Autodesk Fusion 360 part; units mm, degrees
(part 2 of 3)
sketch "spacer_pads" plane through (0, 0, 7.25) normal (0, 0, 1) x (1, 0, 0) in component "drop_plate"
  line L0 (-80, -68) -> (-77, -68)
  line L1 (-77, -68) -> (-77, -62)
  line L2 (-77, -62) -> (-80, -62)
  line L3 (-80, -62) -> (-80, -68)
  line L4 (-53, -68) -> (-50, -68)
  line L5 (-50, -68) -> (-50, -62)
  line L6 (-50, -62) -> (-53, -62)
  line L7 (-53, -62) -> (-53, -68)
  line L8 (-68, -80) -> (-62, -80)
  line L9 (-62, -80) -> (-62, -77)
  line L10 (-62, -77) -> (-68, -77)
  line L11 (-68, -77) -> (-68, -80)
  line L12 (-68, -53) -> (-62, -53)
  line L13 (-62, -53) -> (-62, -50)
  line L14 (-62, -50) -> (-68, -50)
  line L15 (-68, -50) -> (-68, -53)
  line L16 (-80, -35.5) -> (-77, -35.5)
  line L17 (-77, -35.5) -> (-77, -29.5)
  line L18 (-77, -29.5) -> (-80, -29.5)
  line L19 (-80, -29.5) -> (-80, -35.5)
  line L20 (-53, -35.5) -> (-50, -35.5)
  line L21 (-50, -35.5) -> (-50, -29.5)
  line L22 (-50, -29.5) -> (-53, -29.5)
  line L23 (-53, -29.5) -> (-53, -35.5)
  line L24 (-68, -47.5) -> (-62, -47.5)
  line L25 (-62, -47.5) -> (-62, -44.5)
  line L26 (-62, -44.5) -> (-68, -44.5)
  line L27 (-68, -44.5) -> (-68, -47.5)
  line L28 (-68, -20.5) -> (-62, -20.5)
  line L29 (-62, -20.5) -> (-62, -17.5)
  line L30 (-62, -17.5) -> (-68, -17.5)
  line L31 (-68, -17.5) -> (-68, -20.5)
  line L32 (-80, -3) -> (-77, -3)
  line L33 (-77, -3) -> (-77, 3)
  line L34 (-77, 3) -> (-80, 3)
  line L35 (-80, 3) -> (-80, -3)
  line L36 (-53, -3) -> (-50, -3)
  line L37 (-50, -3) -> (-50, 3)
  line L38 (-50, 3) -> (-53, 3)
  line L39 (-53, 3) -> (-53, -3)
  line L40 (-68, -15) -> (-62, -15)
  line L41 (-62, -15) -> (-62, -12)
  line L42 (-62, -12) -> (-68, -12)
  line L43 (-68, -12) -> (-68, -15)
  line L44 (-68, 12) -> (-62, 12)
  line L45 (-62, 12) -> (-62, 15)
  line L46 (-62, 15) -> (-68, 15)
  line L47 (-68, 15) -> (-68, 12)
  line L48 (-80, 29.5) -> (-77, 29.5)
  line L49 (-77, 29.5) -> (-77, 35.5)
  line L50 (-77, 35.5) -> (-80, 35.5)
  line L51 (-80, 35.5) -> (-80, 29.5)
  line L52 (-53, 29.5) -> (-50, 29.5)
  line L53 (-50, 29.5) -> (-50, 35.5)
  line L54 (-50, 35.5) -> (-53, 35.5)
  line L55 (-53, 35.5) -> (-53, 29.5)
  line L56 (-68, 17.5) -> (-62, 17.5)
  line L57 (-62, 17.5) -> (-62, 20.5)
  line L58 (-62, 20.5) -> (-68, 20.5)
  line L59 (-68, 20.5) -> (-68, 17.5)
  line L60 (-68, 44.5) -> (-62, 44.5)
  line L61 (-62, 44.5) -> (-62, 47.5)
  line L62 (-62, 47.5) -> (-68, 47.5)
  line L63 (-68, 47.5) -> (-68, 44.5)
  line L64 (-80, 62) -> (-77, 62)
  line L65 (-77, 62) -> (-77, 68)
  line L66 (-77, 68) -> (-80, 68)
  line L67 (-80, 68) -> (-80, 62)
  line L68 (-53, 62) -> (-50, 62)
  line L69 (-50, 62) -> (-50, 68)
  line L70 (-50, 68) -> (-53, 68)
  line L71 (-53, 68) -> (-53, 62)
  line L72 (-68, 50) -> (-62, 50)
  line L73 (-62, 50) -> (-62, 53)
  line L74 (-62, 53) -> (-68, 53)
  line L75 (-68, 53) -> (-68, 50)
  line L76 (-68, 77) -> (-62, 77)
  line L77 (-62, 77) -> (-62, 80)
  line L78 (-62, 80) -> (-68, 80)
  line L79 (-68, 80) -> (-68, 77)
  line L80 (-47.5, -68) -> (-44.5, -68)
  line L81 (-44.5, -68) -> (-44.5, -62)
  line L82 (-44.5, -62) -> (-47.5, -62)
  line L83 (-47.5, -62) -> (-47.5, -68)
  line L84 (-20.5, -68) -> (-17.5, -68)
  line L85 (-17.5, -68) -> (-17.5, -62)
  line L86 (-17.5, -62) -> (-20.5, -62)
  line L87 (-20.5, -62) -> (-20.5, -68)
  line L88 (-35.5, -80) -> (-29.5, -80)
  line L89 (-29.5, -80) -> (-29.5, -77)
  line L90 (-29.5, -77) -> (-35.5, -77)
  line L91 (-35.5, -77) -> (-35.5, -80)
  line L92 (-35.5, -53) -> (-29.5, -53)
  line L93 (-29.5, -53) -> (-29.5, -50)
  line L94 (-29.5, -50) -> (-35.5, -50)
  line L95 (-35.5, -50) -> (-35.5, -53)
  line L96 (-47.5, -35.5) -> (-44.5, -35.5)
  line L97 (-44.5, -35.5) -> (-44.5, -29.5)
  line L98 (-44.5, -29.5) -> (-47.5, -29.5)
  line L99 (-47.5, -29.5) -> (-47.5, -35.5)
  line L100 (-20.5, -35.5) -> (-17.5, -35.5)
  line L101 (-17.5, -35.5) -> (-17.5, -29.5)
  line L102 (-17.5, -29.5) -> (-20.5, -29.5)
  line L103 (-20.5, -29.5) -> (-20.5, -35.5)
  line L104 (-35.5, -47.5) -> (-29.5, -47.5)
  line L105 (-29.5, -47.5) -> (-29.5, -44.5)
  line L106 (-29.5, -44.5) -> (-35.5, -44.5)
  line L107 (-35.5, -44.5) -> (-35.5, -47.5)
  line L108 (-35.5, -20.5) -> (-29.5, -20.5)
  line L109 (-29.5, -20.5) -> (-29.5, -17.5)
  line L110 (-29.5, -17.5) -> (-35.5, -17.5)
  line L111 (-35.5, -17.5) -> (-35.5, -20.5)
  line L112 (-47.5, -3) -> (-44.5, -3)
  line L113 (-44.5, -3) -> (-44.5, 3)
  line L114 (-44.5, 3) -> (-47.5, 3)
  line L115 (-47.5, 3) -> (-47.5, -3)
  line L116 (-20.5, -3) -> (-17.5, -3)
  line L117 (-17.5, -3) -> (-17.5, 3)
  line L118 (-17.5, 3) -> (-20.5, 3)
  line L119 (-20.5, 3) -> (-20.5, -3)
  line L120 (-35.5, -15) -> (-29.5, -15)
  line L121 (-29.5, -15) -> (-29.5, -12)
  line L122 (-29.5, -12) -> (-35.5, -12)
  line L123 (-35.5, -12) -> (-35.5, -15)
  line L124 (-35.5, 12) -> (-29.5, 12)
  line L125 (-29.5, 12) -> (-29.5, 15)
  line L126 (-29.5, 15) -> (-35.5, 15)
  line L127 (-35.5, 15) -> (-35.5, 12)
  line L128 (-47.5, 29.5) -> (-44.5, 29.5)
  line L129 (-44.5, 29.5) -> (-44.5, 35.5)
  line L130 (-44.5, 35.5) -> (-47.5, 35.5)
  line L131 (-47.5, 35.5) -> (-47.5, 29.5)
  line L132 (-20.5, 29.5) -> (-17.5, 29.5)
  line L133 (-17.5, 29.5) -> (-17.5, 35.5)
  line L134 (-17.5, 35.5) -> (-20.5, 35.5)
  line L135 (-20.5, 35.5) -> (-20.5, 29.5)
  line L136 (-35.5, 17.5) -> (-29.5, 17.5)
  line L137 (-29.5, 17.5) -> (-29.5, 20.5)
  line L138 (-29.5, 20.5) -> (-35.5, 20.5)
  line L139 (-35.5, 20.5) -> (-35.5, 17.5)
  line L140 (-35.5, 44.5) -> (-29.5, 44.5)
  line L141 (-29.5, 44.5) -> (-29.5, 47.5)
  line L142 (-29.5, 47.5) -> (-35.5, 47.5)
  line L143 (-35.5, 47.5) -> (-35.5, 44.5)
  line L144 (-47.5, 62) -> (-44.5, 62)
  line L145 (-44.5, 62) -> (-44.5, 68)
  line L146 (-44.5, 68) -> (-47.5, 68)
  line L147 (-47.5, 68) -> (-47.5, 62)
  line L148 (-20.5, 62) -> (-17.5, 62)
  line L149 (-17.5, 62) -> (-17.5, 68)
  line L150 (-17.5, 68) -> (-20.5, 68)
  line L151 (-20.5, 68) -> (-20.5, 62)
  line L152 (-35.5, 50) -> (-29.5, 50)
  line L153 (-29.5, 50) -> (-29.5, 53)
  line L154 (-29.5, 53) -> (-35.5, 53)
  line L155 (-35.5, 53) -> (-35.5, 50)
  line L156 (-35.5, 77) -> (-29.5, 77)
  line L157 (-29.5, 77) -> (-29.5, 80)
  line L158 (-29.5, 80) -> (-35.5, 80)
  line L159 (-35.5, 80) -> (-35.5, 77)
  line L160 (-15, -68) -> (-12, -68)
  line L161 (-12, -68) -> (-12, -62)
  line L162 (-12, -62) -> (-15, -62)
  line L163 (-15, -62) -> (-15, -68)
  line L164 (12, -68) -> (15, -68)
  line L165 (15, -68) -> (15, -62)
  line L166 (15, -62) -> (12, -62)
  line L167 (12, -62) -> (12, -68)
  line L168 (-3, -80) -> (3, -80)
  line L169 (3, -80) -> (3, -77)
  line L170 (3, -77) -> (-3, -77)
  line L171 (-3, -77) -> (-3, -80)
  line L172 (-3, -53) -> (3, -53)
  line L173 (3, -53) -> (3, -50)
  line L174 (3, -50) -> (-3, -50)
  line L175 (-3, -50) -> (-3, -53)
  line L176 (-15, -35.5) -> (-12, -35.5)
  line L177 (-12, -35.5) -> (-12, -29.5)
  line L178 (-12, -29.5) -> (-15, -29.5)
  line L179 (-15, -29.5) -> (-15, -35.5)
  line L180 (12, -35.5) -> (15, -35.5)
  line L181 (15, -35.5) -> (15, -29.5)
  line L182 (15, -29.5) -> (12, -29.5)
  line L183 (12, -29.5) -> (12, -35.5)
  line L184 (-3, -47.5) -> (3, -47.5)
  line L185 (3, -47.5) -> (3, -44.5)
  line L186 (3, -44.5) -> (-3, -44.5)
  line L187 (-3, -44.5) -> (-3, -47.5)
  line L188 (-3, -20.5) -> (3, -20.5)
  line L189 (3, -20.5) -> (3, -17.5)
  line L190 (3, -17.5) -> (-3, -17.5)
  line L191 (-3, -17.5) -> (-3, -20.5)
  line L192 (-15, -3) -> (-12, -3)
  line L193 (-12, -3) -> (-12, 3)
  line L194 (-12, 3) -> (-15, 3)
  line L195 (-15, 3) -> (-15, -3)
  line L196 (12, -3) -> (15, -3)
  line L197 (15, -3) -> (15, 3)
  line L198 (15, 3) -> (12, 3)
  line L199 (12, 3) -> (12, -3)
  line L200 (-3, -15) -> (3, -15)
  line L201 (3, -15) -> (3, -12)
  line L202 (3, -12) -> (-3, -12)
  line L203 (-3, -12) -> (-3, -15)
  line L204 (-3, 12) -> (3, 12)
  line L205 (3, 12) -> (3, 15)
  line L206 (3, 15) -> (-3, 15)
  line L207 (-3, 15) -> (-3, 12)
  line L208 (-15, 29.5) -> (-12, 29.5)
  line L209 (-12, 29.5) -> (-12, 35.5)
  line L210 (-12, 35.5) -> (-15, 35.5)
  line L211 (-15, 35.5) -> (-15, 29.5)
  line L212 (12, 29.5) -> (15, 29.5)
  line L213 (15, 29.5) -> (15, 35.5)
  line L214 (15, 35.5) -> (12, 35.5)
  line L215 (12, 35.5) -> (12, 29.5)
  line L216 (-3, 17.5) -> (3, 17.5)
  line L217 (3, 17.5) -> (3, 20.5)
  line L218 (3, 20.5) -> (-3, 20.5)
  line L219 (-3, 20.5) -> (-3, 17.5)
  line L220 (-3, 44.5) -> (3, 44.5)
  line L221 (3, 44.5) -> (3, 47.5)
  line L222 (3, 47.5) -> (-3, 47.5)
  line L223 (-3, 47.5) -> (-3, 44.5)
  line L224 (-15, 62) -> (-12, 62)
  line L225 (-12, 62) -> (-12, 68)
  line L226 (-12, 68) -> (-15, 68)
  line L227 (-15, 68) -> (-15, 62)
  line L228 (12, 62) -> (15, 62)
  line L229 (15, 62) -> (15, 68)
  line L230 (15, 68) -> (12, 68)
  line L231 (12, 68) -> (12, 62)
  line L232 (-3, 50) -> (3, 50)
  line L233 (3, 50) -> (3, 53)
  line L234 (3, 53) -> (-3, 53)
  line L235 (-3, 53) -> (-3, 50)
  line L236 (-3, 77) -> (3, 77)
  line L237 (3, 77) -> (3, 80)
  line L238 (3, 80) -> (-3, 80)
  line L239 (-3, 80) -> (-3, 77)
  line L240 (17.5, -68) -> (20.5, -68)
  line L241 (20.5, -68) -> (20.5, -62)
  line L242 (20.5, -62) -> (17.5, -62)
  line L243 (17.5, -62) -> (17.5, -68)
  line L244 (44.5, -68) -> (47.5, -68)
  line L245 (47.5, -68) -> (47.5, -62)
  line L246 (47.5, -62) -> (44.5, -62)
  line L247 (44.5, -62) -> (44.5, -68)
  line L248 (29.5, -80) -> (35.5, -80)
  line L249 (35.5, -80) -> (35.5, -77)
  line L250 (35.5, -77) -> (29.5, -77)
  line L251 (29.5, -77) -> (29.5, -80)
  line L252 (29.5, -53) -> (35.5, -53)
  line L253 (35.5, -53) -> (35.5, -50)
  line L254 (35.5, -50) -> (29.5, -50)
  line L255 (29.5, -50) -> (29.5, -53)
  line L256 (17.5, -35.5) -> (20.5, -35.5)
  line L257 (20.5, -35.5) -> (20.5, -29.5)
  line L258 (20.5, -29.5) -> (17.5, -29.5)
  line L259 (17.5, -29.5) -> (17.5, -35.5)
  line L260 (44.5, -35.5) -> (47.5, -35.5)
  line L261 (47.5, -35.5) -> (47.5, -29.5)
  line L262 (47.5, -29.5) -> (44.5, -29.5)
  line L263 (44.5, -29.5) -> (44.5, -35.5)
  line L264 (29.5, -47.5) -> (35.5, -47.5)
  line L265 (35.5, -47.5) -> (35.5, -44.5)
  line L266 (35.5, -44.5) -> (29.5, -44.5)
  line L267 (29.5, -44.5) -> (29.5, -47.5)
  line L268 (29.5, -20.5) -> (35.5, -20.5)
  line L269 (35.5, -20.5) -> (35.5, -17.5)
  line L270 (35.5, -17.5) -> (29.5, -17.5)
  line L271 (29.5, -17.5) -> (29.5, -20.5)
  line L272 (17.5, -3) -> (20.5, -3)
  line L273 (20.5, -3) -> (20.5, 3)
  line L274 (20.5, 3) -> (17.5, 3)
  line L275 (17.5, 3) -> (17.5, -3)
  line L276 (44.5, -3) -> (47.5, -3)
  line L277 (47.5, -3) -> (47.5, 3)
  line L278 (47.5, 3) -> (44.5, 3)
  line L279 (44.5, 3) -> (44.5, -3)
  line L280 (29.5, -15) -> (35.5, -15)
  line L281 (35.5, -15) -> (35.5, -12)
  line L282 (35.5, -12) -> (29.5, -12)
  line L283 (29.5, -12) -> (29.5, -15)
  line L284 (29.5, 12) -> (35.5, 12)
  line L285 (35.5, 12) -> (35.5, 15)
  line L286 (35.5, 15) -> (29.5, 15)
  line L287 (29.5, 15) -> (29.5, 12)
  line L288 (17.5, 29.5) -> (20.5, 29.5)
  line L289 (20.5, 29.5) -> (20.5, 35.5)
  line L290 (20.5, 35.5) -> (17.5, 35.5)
  line L291 (17.5, 35.5) -> (17.5, 29.5)
  line L292 (44.5, 29.5) -> (47.5, 29.5)
  line L293 (47.5, 29.5) -> (47.5, 35.5)
  line L294 (47.5, 35.5) -> (44.5, 35.5)
  line L295 (44.5, 35.5) -> (44.5, 29.5)
  line L296 (29.5, 17.5) -> (35.5, 17.5)
  line L297 (35.5, 17.5) -> (35.5, 20.5)
  line L298 (35.5, 20.5) -> (29.5, 20.5)
  line L299 (29.5, 20.5) -> (29.5, 17.5)
  line L300 (29.5, 44.5) -> (35.5, 44.5)
  line L301 (35.5, 44.5) -> (35.5, 47.5)
  line L302 (35.5, 47.5) -> (29.5, 47.5)
  line L303 (29.5, 47.5) -> (29.5, 44.5)
  line L304 (17.5, 62) -> (20.5, 62)
  line L305 (20.5, 62) -> (20.5, 68)
  line L306 (20.5, 68) -> (17.5, 68)
  line L307 (17.5, 68) -> (17.5, 62)
  line L308 (44.5, 62) -> (47.5, 62)
  line L309 (47.5, 62) -> (47.5, 68)
  line L310 (47.5, 68) -> (44.5, 68)
  line L311 (44.5, 68) -> (44.5, 62)
  line L312 (29.5, 50) -> (35.5, 50)
  line L313 (35.5, 50) -> (35.5, 53)
  line L314 (35.5, 53) -> (29.5, 53)
  line L315 (29.5, 53) -> (29.5, 50)
  line L316 (29.5, 77) -> (35.5, 77)
  line L317 (35.5, 77) -> (35.5, 80)
  line L318 (35.5, 80) -> (29.5, 80)
  line L319 (29.5, 80) -> (29.5, 77)
  line L320 (50, -68) -> (53, -68)
  line L321 (53, -68) -> (53, -62)
  line L322 (53, -62) -> (50, -62)
  line L323 (50, -62) -> (50, -68)
  line L324 (77, -68) -> (80, -68)
  line L325 (80, -68) -> (80, -62)
  line L326 (80, -62) -> (77, -62)
  line L327 (77, -62) -> (77, -68)
  line L328 (62, -80) -> (68, -80)
  line L329 (68, -80) -> (68, -77)
  line L330 (68, -77) -> (62, -77)
  line L331 (62, -77) -> (62, -80)
  line L332 (62, -53) -> (68, -53)
  line L333 (68, -53) -> (68, -50)
  line L334 (68, -50) -> (62, -50)
  line L335 (62, -50) -> (62, -53)
  line L336 (50, -35.5) -> (53, -35.5)
  line L337 (53, -35.5) -> (53, -29.5)
  line L338 (53, -29.5) -> (50, -29.5)
  line L339 (50, -29.5) -> (50, -35.5)
  line L340 (77, -35.5) -> (80, -35.5)
  line L341 (80, -35.5) -> (80, -29.5)
  line L342 (80, -29.5) -> (77, -29.5)
  line L343 (77, -29.5) -> (77, -35.5)
  line L344 (62, -47.5) -> (68, -47.5)
  line L345 (68, -47.5) -> (68, -44.5)
  line L346 (68, -44.5) -> (62, -44.5)
  line L347 (62, -44.5) -> (62, -47.5)
  line L348 (62, -20.5) -> (68, -20.5)
  line L349 (68, -20.5) -> (68, -17.5)
  line L350 (68, -17.5) -> (62, -17.5)
  line L351 (62, -17.5) -> (62, -20.5)
  line L352 (50, -3) -> (53, -3)
  line L353 (53, -3) -> (53, 3)
  line L354 (53, 3) -> (50, 3)
  line L355 (50, 3) -> (50, -3)
  line L356 (77, -3) -> (80, -3)
  line L357 (80, -3) -> (80, 3)
  line L358 (80, 3) -> (77, 3)
  line L359 (77, 3) -> (77, -3)
  line L360 (62, -15) -> (68, -15)
  line L361 (68, -15) -> (68, -12)
  line L362 (68, -12) -> (62, -12)
  line L363 (62, -12) -> (62, -15)
  line L364 (62, 12) -> (68, 12)
  line L365 (68, 12) -> (68, 15)
  line L366 (68, 15) -> (62, 15)
  line L367 (62, 15) -> (62, 12)
  line L368 (50, 29.5) -> (53, 29.5)
  line L369 (53, 29.5) -> (53, 35.5)
  line L370 (53, 35.5) -> (50, 35.5)
  line L371 (50, 35.5) -> (50, 29.5)
  line L372 (77, 29.5) -> (80, 29.5)
  line L373 (80, 29.5) -> (80, 35.5)
  line L374 (80, 35.5) -> (77, 35.5)
  line L375 (77, 35.5) -> (77, 29.5)
  line L376 (62, 17.5) -> (68, 17.5)
  line L377 (68, 17.5) -> (68, 20.5)
  line L378 (68, 20.5) -> (62, 20.5)
  line L379 (62, 20.5) -> (62, 17.5)
  line L380 (62, 44.5) -> (68, 44.5)
  line L381 (68, 44.5) -> (68, 47.5)
  line L382 (68, 47.5) -> (62, 47.5)
  line L383 (62, 47.5) -> (62, 44.5)
  line L384 (50, 62) -> (53, 62)
  line L385 (53, 62) -> (53, 68)
  line L386 (53, 68) -> (50, 68)
  line L387 (50, 68) -> (50, 62)
  line L388 (77, 62) -> (80, 62)
  line L389 (80, 62) -> (80, 68)
  line L390 (80, 68) -> (77, 68)
  line L391 (77, 68) -> (77, 62)
  line L392 (62, 50) -> (68, 50)
  line L393 (68, 50) -> (68, 53)
  line L394 (68, 53) -> (62, 53)
  line L395 (62, 53) -> (62, 50)
  line L396 (62, 77) -> (68, 77)
  line L397 (68, 77) -> (68, 80)
  line L398 (68, 80) -> (62, 80)
  line L399 (62, 80) -> (62, 77)
extrude "spacer_pads (1)" add sketch "spacer_pads" along normal blind 0.6 bodies 1 in component "drop_plate"
ref_plane "WorkPlane6" through (0, 0, 7.25) normal (0, 0, 1) x (1, 0, 0) in component "drop_plate"
sketch "locating_posts" plane through (0, 0, 7.25) normal (0, 0, 1) x (1, 0, 0) in component "drop_plate"
  line L0 (-82.2, -82.2) -> (-80.3, -82.2)
  line L1 (-80.3, -82.2) -> (-80.3, -80.3)
  line L2 (-80.3, -80.3) -> (-82.2, -80.3)
  line L3 (-82.2, -80.3) -> (-82.2, -82.2)
  line L4 (-82.2, -49.7) -> (-80.3, -49.7)
  line L5 (-80.3, -49.7) -> (-80.3, -47.8)
  line L6 (-80.3, -47.8) -> (-82.2, -47.8)
  line L7 (-82.2, -47.8) -> (-82.2, -49.7)
  line L8 (-82.2, -17.2) -> (-80.3, -17.2)
  line L9 (-80.3, -17.2) -> (-80.3, -15.3)
  line L10 (-80.3, -15.3) -> (-82.2, -15.3)
  line L11 (-82.2, -15.3) -> (-82.2, -17.2)
  line L12 (-82.2, 15.3) -> (-80.3, 15.3)
  line L13 (-80.3, 15.3) -> (-80.3, 17.2)
  line L14 (-80.3, 17.2) -> (-82.2, 17.2)
  line L15 (-82.2, 17.2) -> (-82.2, 15.3)
  line L16 (-82.2, 47.8) -> (-80.3, 47.8)
  line L17 (-80.3, 47.8) -> (-80.3, 49.7)
  line L18 (-80.3, 49.7) -> (-82.2, 49.7)
  line L19 (-82.2, 49.7) -> (-82.2, 47.8)
  line L20 (-82.2, 80.3) -> (-80.3, 80.3)
  line L21 (-80.3, 80.3) -> (-80.3, 82.2)
  line L22 (-80.3, 82.2) -> (-82.2, 82.2)
  line L23 (-82.2, 82.2) -> (-82.2, 80.3)
  line L24 (-49.7, -82.2) -> (-47.8, -82.2)
  line L25 (-47.8, -82.2) -> (-47.8, -80.3)
  line L26 (-47.8, -80.3) -> (-49.7, -80.3)
  line L27 (-49.7, -80.3) -> (-49.7, -82.2)
  line L28 (-49.7, -49.7) -> (-47.8, -49.7)
  line L29 (-47.8, -49.7) -> (-47.8, -47.8)
  line L30 (-47.8, -47.8) -> (-49.7, -47.8)
  line L31 (-49.7, -47.8) -> (-49.7, -49.7)
  line L32 (-49.7, -17.2) -> (-47.8, -17.2)
  line L33 (-47.8, -17.2) -> (-47.8, -15.3)
  line L34 (-47.8, -15.3) -> (-49.7, -15.3)
  line L35 (-49.7, -15.3) -> (-49.7, -17.2)
  line L36 (-49.7, 15.3) -> (-47.8, 15.3)
  line L37 (-47.8, 15.3) -> (-47.8, 17.2)
  line L38 (-47.8, 17.2) -> (-49.7, 17.2)
  line L39 (-49.7, 17.2) -> (-49.7, 15.3)
  line L40 (-49.7, 47.8) -> (-47.8, 47.8)
  line L41 (-47.8, 47.8) -> (-47.8, 49.7)
  line L42 (-47.8, 49.7) -> (-49.7, 49.7)
  line L43 (-49.7, 49.7) -> (-49.7, 47.8)
  line L44 (-49.7, 80.3) -> (-47.8, 80.3)
  line L45 (-47.8, 80.3) -> (-47.8, 82.2)
  line L46 (-47.8, 82.2) -> (-49.7, 82.2)
  line L47 (-49.7, 82.2) -> (-49.7, 80.3)
  line L48 (-17.2, -82.2) -> (-15.3, -82.2)
  line L49 (-15.3, -82.2) -> (-15.3, -80.3)
  line L50 (-15.3, -80.3) -> (-17.2, -80.3)
  line L51 (-17.2, -80.3) -> (-17.2, -82.2)
  line L52 (-17.2, -49.7) -> (-15.3, -49.7)
  line L53 (-15.3, -49.7) -> (-15.3, -47.8)
  line L54 (-15.3, -47.8) -> (-17.2, -47.8)
  line L55 (-17.2, -47.8) -> (-17.2, -49.7)
  line L56 (-17.2, -17.2) -> (-15.3, -17.2)
  line L57 (-15.3, -17.2) -> (-15.3, -15.3)
  line L58 (-15.3, -15.3) -> (-17.2, -15.3)
  line L59 (-17.2, -15.3) -> (-17.2, -17.2)
  line L60 (-17.2, 15.3) -> (-15.3, 15.3)
  line L61 (-15.3, 15.3) -> (-15.3, 17.2)
  line L62 (-15.3, 17.2) -> (-17.2, 17.2)
  line L63 (-17.2, 17.2) -> (-17.2, 15.3)
  line L64 (-17.2, 47.8) -> (-15.3, 47.8)
  line L65 (-15.3, 47.8) -> (-15.3, 49.7)
  line L66 (-15.3, 49.7) -> (-17.2, 49.7)
  line L67 (-17.2, 49.7) -> (-17.2, 47.8)
  line L68 (-17.2, 80.3) -> (-15.3, 80.3)
  line L69 (-15.3, 80.3) -> (-15.3, 82.2)
  line L70 (-15.3, 82.2) -> (-17.2, 82.2)
  line L71 (-17.2, 82.2) -> (-17.2, 80.3)
  line L72 (15.3, -82.2) -> (17.2, -82.2)
  line L73 (17.2, -82.2) -> (17.2, -80.3)
  line L74 (17.2, -80.3) -> (15.3, -80.3)
  line L75 (15.3, -80.3) -> (15.3, -82.2)
  line L76 (15.3, -49.7) -> (17.2, -49.7)
  line L77 (17.2, -49.7) -> (17.2, -47.8)
  line L78 (17.2, -47.8) -> (15.3, -47.8)
  line L79 (15.3, -47.8) -> (15.3, -49.7)
  line L80 (15.3, -17.2) -> (17.2, -17.2)
  line L81 (17.2, -17.2) -> (17.2, -15.3)
  line L82 (17.2, -15.3) -> (15.3, -15.3)
  line L83 (15.3, -15.3) -> (15.3, -17.2)
  line L84 (15.3, 15.3) -> (17.2, 15.3)
  line L85 (17.2, 15.3) -> (17.2, 17.2)
  line L86 (17.2, 17.2) -> (15.3, 17.2)
  line L87 (15.3, 17.2) -> (15.3, 15.3)
  line L88 (15.3, 47.8) -> (17.2, 47.8)
  line L89 (17.2, 47.8) -> (17.2, 49.7)
  line L90 (17.2, 49.7) -> (15.3, 49.7)
  line L91 (15.3, 49.7) -> (15.3, 47.8)
  line L92 (15.3, 80.3) -> (17.2, 80.3)
  line L93 (17.2, 80.3) -> (17.2, 82.2)
  line L94 (17.2, 82.2) -> (15.3, 82.2)
  line L95 (15.3, 82.2) -> (15.3, 80.3)
  line L96 (47.8, -82.2) -> (49.7, -82.2)
  line L97 (49.7, -82.2) -> (49.7, -80.3)
  line L98 (49.7, -80.3) -> (47.8, -80.3)
  line L99 (47.8, -80.3) -> (47.8, -82.2)
  line L100 (47.8, -49.7) -> (49.7, -49.7)
  line L101 (49.7, -49.7) -> (49.7, -47.8)
  line L102 (49.7, -47.8) -> (47.8, -47.8)
  line L103 (47.8, -47.8) -> (47.8, -49.7)
  line L104 (47.8, -17.2) -> (49.7, -17.2)
  line L105 (49.7, -17.2) -> (49.7, -15.3)
  line L106 (49.7, -15.3) -> (47.8, -15.3)
  line L107 (47.8, -15.3) -> (47.8, -17.2)
  line L108 (47.8, 15.3) -> (49.7, 15.3)
  line L109 (49.7, 15.3) -> (49.7, 17.2)
  line L110 (49.7, 17.2) -> (47.8, 17.2)
  line L111 (47.8, 17.2) -> (47.8, 15.3)
  line L112 (47.8, 47.8) -> (49.7, 47.8)
  line L113 (49.7, 47.8) -> (49.7, 49.7)
  line L114 (49.7, 49.7) -> (47.8, 49.7)
  line L115 (47.8, 49.7) -> (47.8, 47.8)
  line L116 (47.8, 80.3) -> (49.7, 80.3)
  line L117 (49.7, 80.3) -> (49.7, 82.2)
  line L118 (49.7, 82.2) -> (47.8, 82.2)
  line L119 (47.8, 82.2) -> (47.8, 80.3)
  line L120 (80.3, -82.2) -> (82.2, -82.2)
  line L121 (82.2, -82.2) -> (82.2, -80.3)
  line L122 (82.2, -80.3) -> (80.3, -80.3)
  line L123 (80.3, -80.3) -> (80.3, -82.2)
  line L124 (80.3, -49.7) -> (82.2, -49.7)
  line L125 (82.2, -49.7) -> (82.2, -47.8)
  line L126 (82.2, -47.8) -> (80.3, -47.8)
  line L127 (80.3, -47.8) -> (80.3, -49.7)
  line L128 (80.3, -17.2) -> (82.2, -17.2)
  line L129 (82.2, -17.2) -> (82.2, -15.3)
  line L130 (82.2, -15.3) -> (80.3, -15.3)
  line L131 (80.3, -15.3) -> (80.3, -17.2)
  line L132 (80.3, 15.3) -> (82.2, 15.3)
  line L133 (82.2, 15.3) -> (82.2, 17.2)
  line L134 (82.2, 17.2) -> (80.3, 17.2)
  line L135 (80.3, 17.2) -> (80.3, 15.3)
  line L136 (80.3, 47.8) -> (82.2, 47.8)
  line L137 (82.2, 47.8) -> (82.2, 49.7)
  line L138 (82.2, 49.7) -> (80.3, 49.7)
  line L139 (80.3, 49.7) -> (80.3, 47.8)
  line L140 (80.3, 80.3) -> (82.2, 80.3)
  line L141 (82.2, 80.3) -> (82.2, 82.2)
  line L142 (82.2, 82.2) -> (80.3, 82.2)
  line L143 (80.3, 82.2) -> (80.3, 80.3)
extrude "locating_posts (1)" add sketch "locating_posts" along normal blind 2.4 bodies 1 in component "drop_plate"
ref_plane "WorkPlane7" through (0, 0, 9.65) normal (0, 0, 1) x (1, 0, 0) in component "drop_plate"
sketch "orientation_post" plane through (0, 0, 9.65) normal (0, 0, 1) x (1, 0, 0) in component "drop_plate"
  line L0 (-82.2, -82.2) -> (-80.3, -82.2)
  line L1 (-80.3, -82.2) -> (-80.3, -80.3)
  line L2 (-80.3, -80.3) -> (-82.2, -80.3)
  line L3 (-82.2, -80.3) -> (-82.2, -82.2)
extrude "orientation_post (1)" add sketch "orientation_post" along normal blind 3 bodies 1 in component "drop_plate"
ref_plane "WorkPlane8" through (0, 0, 7.25) normal (0, 0, 1) x (1, 0, 0) in component "drop_plate"
sketch "scale_crosses" plane through (0, 0, 7.25) normal (0, 0, 1) x (1, 0, 0) in component "drop_plate"
  line L0 (-78, -76.3) -> (-74, -76.3)
  line L1 (-74, -76.3) -> (-74, -75.7)
  line L2 (-74, -75.7) -> (-78, -75.7)
  line L3 (-78, -75.7) -> (-78, -76.3)
  line L4 (-76.3, -78) -> (-75.7, -78)
  line L5 (-75.7, -78) -> (-75.7, -74)
  line L6 (-75.7, -74) -> (-76.3, -74)
  line L7 (-76.3, -74) -> (-76.3, -78)
  line L8 (-78, -54.3) -> (-74, -54.3)
  line L9 (-74, -54.3) -> (-74, -53.7)
  line L10 (-74, -53.7) -> (-78, -53.7)
  line L11 (-78, -53.7) -> (-78, -54.3)
  line L12 (-76.3, -56) -> (-75.7, -56)
  line L13 (-75.7, -56) -> (-75.7, -52)
  line L14 (-75.7, -52) -> (-76.3, -52)
  line L15 (-76.3, -52) -> (-76.3, -56)
  line L16 (-56, -76.3) -> (-52, -76.3)
  line L17 (-52, -76.3) -> (-52, -75.7)
  line L18 (-52, -75.7) -> (-56, -75.7)
  line L19 (-56, -75.7) -> (-56, -76.3)
  line L20 (-54.3, -78) -> (-53.7, -78)
  line L21 (-53.7, -78) -> (-53.7, -74)
  line L22 (-53.7, -74) -> (-54.3, -74)
  line L23 (-54.3, -74) -> (-54.3, -78)
  line L24 (-56, -54.3) -> (-52, -54.3)
  line L25 (-52, -54.3) -> (-52, -53.7)
  line L26 (-52, -53.7) -> (-56, -53.7)
  line L27 (-56, -53.7) -> (-56, -54.3)
  line L28 (-54.3, -56) -> (-53.7, -56)
  line L29 (-53.7, -56) -> (-53.7, -52)
  line L30 (-53.7, -52) -> (-54.3, -52)
  line L31 (-54.3, -52) -> (-54.3, -56)
  line L32 (-78, -43.8) -> (-74, -43.8)
  line L33 (-74, -43.8) -> (-74, -43.2)
  line L34 (-74, -43.2) -> (-78, -43.2)
  line L35 (-78, -43.2) -> (-78, -43.8)
  line L36 (-76.3, -45.5) -> (-75.7, -45.5)
  line L37 (-75.7, -45.5) -> (-75.7, -41.5)
  line L38 (-75.7, -41.5) -> (-76.3, -41.5)
  line L39 (-76.3, -41.5) -> (-76.3, -45.5)
  line L40 (-78, -21.8) -> (-74, -21.8)
  line L41 (-74, -21.8) -> (-74, -21.2)
  line L42 (-74, -21.2) -> (-78, -21.2)
  line L43 (-78, -21.2) -> (-78, -21.8)
  line L44 (-76.3, -23.5) -> (-75.7, -23.5)
  line L45 (-75.7, -23.5) -> (-75.7, -19.5)
  line L46 (-75.7, -19.5) -> (-76.3, -19.5)
  line L47 (-76.3, -19.5) -> (-76.3, -23.5)
  line L48 (-56, -43.8) -> (-52, -43.8)
  line L49 (-52, -43.8) -> (-52, -43.2)
  line L50 (-52, -43.2) -> (-56, -43.2)
  line L51 (-56, -43.2) -> (-56, -43.8)
  line L52 (-54.3, -45.5) -> (-53.7, -45.5)
  line L53 (-53.7, -45.5) -> (-53.7, -41.5)
  line L54 (-53.7, -41.5) -> (-54.3, -41.5)
  line L55 (-54.3, -41.5) -> (-54.3, -45.5)
  line L56 (-56, -21.8) -> (-52, -21.8)
  line L57 (-52, -21.8) -> (-52, -21.2)
  line L58 (-52, -21.2) -> (-56, -21.2)
  line L59 (-56, -21.2) -> (-56, -21.8)
  line L60 (-54.3, -23.5) -> (-53.7, -23.5)
  line L61 (-53.7, -23.5) -> (-53.7, -19.5)
  line L62 (-53.7, -19.5) -> (-54.3, -19.5)
  line L63 (-54.3, -19.5) -> (-54.3, -23.5)
  line L64 (-78, -11.3) -> (-74, -11.3)
  line L65 (-74, -11.3) -> (-74, -10.7)
  line L66 (-74, -10.7) -> (-78, -10.7)
  line L67 (-78, -10.7) -> (-78, -11.3)
  line L68 (-76.3, -13) -> (-75.7, -13)
  line L69 (-75.7, -13) -> (-75.7, -9)
  line L70 (-75.7, -9) -> (-76.3, -9)
  line L71 (-76.3, -9) -> (-76.3, -13)
  line L72 (-78, 10.7) -> (-74, 10.7)
  line L73 (-74, 10.7) -> (-74, 11.3)
  line L74 (-74, 11.3) -> (-78, 11.3)
  line L75 (-78, 11.3) -> (-78, 10.7)
  line L76 (-76.3, 9) -> (-75.7, 9)
  line L77 (-75.7, 9) -> (-75.7, 13)
  line L78 (-75.7, 13) -> (-76.3, 13)
  line L79 (-76.3, 13) -> (-76.3, 9)
  line L80 (-56, -11.3) -> (-52, -11.3)
  line L81 (-52, -11.3) -> (-52, -10.7)
  line L82 (-52, -10.7) -> (-56, -10.7)
  line L83 (-56, -10.7) -> (-56, -11.3)
  line L84 (-54.3, -13) -> (-53.7, -13)
  line L85 (-53.7, -13) -> (-53.7, -9)
  line L86 (-53.7, -9) -> (-54.3, -9)
  line L87 (-54.3, -9) -> (-54.3, -13)
  line L88 (-56, 10.7) -> (-52, 10.7)
  line L89 (-52, 10.7) -> (-52, 11.3)
  line L90 (-52, 11.3) -> (-56, 11.3)
  line L91 (-56, 11.3) -> (-56, 10.7)
  line L92 (-54.3, 9) -> (-53.7, 9)
  line L93 (-53.7, 9) -> (-53.7, 13)
  line L94 (-53.7, 13) -> (-54.3, 13)
  line L95 (-54.3, 13) -> (-54.3, 9)
  line L96 (-78, 21.2) -> (-74, 21.2)
  line L97 (-74, 21.2) -> (-74, 21.8)
  line L98 (-74, 21.8) -> (-78, 21.8)
  line L99 (-78, 21.8) -> (-78, 21.2)
  line L100 (-76.3, 19.5) -> (-75.7, 19.5)
  line L101 (-75.7, 19.5) -> (-75.7, 23.5)
  line L102 (-75.7, 23.5) -> (-76.3, 23.5)
  line L103 (-76.3, 23.5) -> (-76.3, 19.5)
  line L104 (-78, 43.2) -> (-74, 43.2)
  line L105 (-74, 43.2) -> (-74, 43.8)
  line L106 (-74, 43.8) -> (-78, 43.8)
  line L107 (-78, 43.8) -> (-78, 43.2)
  line L108 (-76.3, 41.5) -> (-75.7, 41.5)
  line L109 (-75.7, 41.5) -> (-75.7, 45.5)
  line L110 (-75.7, 45.5) -> (-76.3, 45.5)
  line L111 (-76.3, 45.5) -> (-76.3, 41.5)
  line L112 (-56, 21.2) -> (-52, 21.2)
  line L113 (-52, 21.2) -> (-52, 21.8)
  line L114 (-52, 21.8) -> (-56, 21.8)
  line L115 (-56, 21.8) -> (-56, 21.2)
  line L116 (-54.3, 19.5) -> (-53.7, 19.5)
  line L117 (-53.7, 19.5) -> (-53.7, 23.5)
  line L118 (-53.7, 23.5) -> (-54.3, 23.5)
  line L119 (-54.3, 23.5) -> (-54.3, 19.5)
  line L120 (-56, 43.2) -> (-52, 43.2)
  line L121 (-52, 43.2) -> (-52, 43.8)
  line L122 (-52, 43.8) -> (-56, 43.8)
  line L123 (-56, 43.8) -> (-56, 43.2)
  line L124 (-54.3, 41.5) -> (-53.7, 41.5)
  line L125 (-53.7, 41.5) -> (-53.7, 45.5)
  line L126 (-53.7, 45.5) -> (-54.3, 45.5)
  line L127 (-54.3, 45.5) -> (-54.3, 41.5)
  line L128 (-78, 53.7) -> (-74, 53.7)
  line L129 (-74, 53.7) -> (-74, 54.3)
  line L130 (-74, 54.3) -> (-78, 54.3)
  line L131 (-78, 54.3) -> (-78, 53.7)
  line L132 (-76.3, 52) -> (-75.7, 52)
  line L133 (-75.7, 52) -> (-75.7, 56)
  line L134 (-75.7, 56) -> (-76.3, 56)
  line L135 (-76.3, 56) -> (-76.3, 52)
  line L136 (-78, 75.7) -> (-74, 75.7)
  line L137 (-74, 75.7) -> (-74, 76.3)
  line L138 (-74, 76.3) -> (-78, 76.3)
  line L139 (-78, 76.3) -> (-78, 75.7)
  line L140 (-76.3, 74) -> (-75.7, 74)
  line L141 (-75.7, 74) -> (-75.7, 78)
  line L142 (-75.7, 78) -> (-76.3, 78)
  line L143 (-76.3, 78) -> (-76.3, 74)
  line L144 (-56, 53.7) -> (-52, 53.7)
  line L145 (-52, 53.7) -> (-52, 54.3)
  line L146 (-52, 54.3) -> (-56, 54.3)
  line L147 (-56, 54.3) -> (-56, 53.7)
  line L148 (-54.3, 52) -> (-53.7, 52)
  line L149 (-53.7, 52) -> (-53.7, 56)
  line L150 (-53.7, 56) -> (-54.3, 56)
  line L151 (-54.3, 56) -> (-54.3, 52)
  line L152 (-56, 75.7) -> (-52, 75.7)
  line L153 (-52, 75.7) -> (-52, 76.3)
  line L154 (-52, 76.3) -> (-56, 76.3)
  line L155 (-56, 76.3) -> (-56, 75.7)
  line L156 (-54.3, 74) -> (-53.7, 74)
  line L157 (-53.7, 74) -> (-53.7, 78)
  line L158 (-53.7, 78) -> (-54.3, 78)
  line L159 (-54.3, 78) -> (-54.3, 74)
  line L160 (-45.5, -76.3) -> (-41.5, -76.3)
  line L161 (-41.5, -76.3) -> (-41.5, -75.7)
  line L162 (-41.5, -75.7) -> (-45.5, -75.7)
  line L163 (-45.5, -75.7) -> (-45.5, -76.3)
  line L164 (-43.8, -78) -> (-43.2, -78)
  line L165 (-43.2, -78) -> (-43.2, -74)
  line L166 (-43.2, -74) -> (-43.8, -74)
  line L167 (-43.8, -74) -> (-43.8, -78)
  line L168 (-45.5, -54.3) -> (-41.5, -54.3)
  line L169 (-41.5, -54.3) -> (-41.5, -53.7)
  line L170 (-41.5, -53.7) -> (-45.5, -53.7)
  line L171 (-45.5, -53.7) -> (-45.5, -54.3)
  line L172 (-43.8, -56) -> (-43.2, -56)
  line L173 (-43.2, -56) -> (-43.2, -52)
  line L174 (-43.2, -52) -> (-43.8, -52)
  line L175 (-43.8, -52) -> (-43.8, -56)
  line L176 (-23.5, -76.3) -> (-19.5, -76.3)
  line L177 (-19.5, -76.3) -> (-19.5, -75.7)
  line L178 (-19.5, -75.7) -> (-23.5, -75.7)
  line L179 (-23.5, -75.7) -> (-23.5, -76.3)
  line L180 (-21.8, -78) -> (-21.2, -78)
  line L181 (-21.2, -78) -> (-21.2, -74)
  line L182 (-21.2, -74) -> (-21.8, -74)
  line L183 (-21.8, -74) -> (-21.8, -78)
  line L184 (-23.5, -54.3) -> (-19.5, -54.3)
  line L185 (-19.5, -54.3) -> (-19.5, -53.7)
  line L186 (-19.5, -53.7) -> (-23.5, -53.7)
  line L187 (-23.5, -53.7) -> (-23.5, -54.3)
  line L188 (-21.8, -56) -> (-21.2, -56)
  line L189 (-21.2, -56) -> (-21.2, -52)
  line L190 (-21.2, -52) -> (-21.8, -52)
  line L191 (-21.8, -52) -> (-21.8, -56)
  line L192 (-45.5, -43.8) -> (-41.5, -43.8)
  line L193 (-41.5, -43.8) -> (-41.5, -43.2)
  line L194 (-41.5, -43.2) -> (-45.5, -43.2)
  line L195 (-45.5, -43.2) -> (-45.5, -43.8)
  line L196 (-43.8, -45.5) -> (-43.2, -45.5)
  line L197 (-43.2, -45.5) -> (-43.2, -41.5)
  line L198 (-43.2, -41.5) -> (-43.8, -41.5)
  line L199 (-43.8, -41.5) -> (-43.8, -45.5)
  line L200 (-45.5, -21.8) -> (-41.5, -21.8)
  line L201 (-41.5, -21.8) -> (-41.5, -21.2)
  line L202 (-41.5, -21.2) -> (-45.5, -21.2)
  line L203 (-45.5, -21.2) -> (-45.5, -21.8)
  line L204 (-43.8, -23.5) -> (-43.2, -23.5)
  line L205 (-43.2, -23.5) -> (-43.2, -19.5)
  line L206 (-43.2, -19.5) -> (-43.8, -19.5)
  line L207 (-43.8, -19.5) -> (-43.8, -23.5)
  line L208 (-23.5, -43.8) -> (-19.5, -43.8)
  line L209 (-19.5, -43.8) -> (-19.5, -43.2)
  line L210 (-19.5, -43.2) -> (-23.5, -43.2)
  line L211 (-23.5, -43.2) -> (-23.5, -43.8)
  line L212 (-21.8, -45.5) -> (-21.2, -45.5)
  line L213 (-21.2, -45.5) -> (-21.2, -41.5)
  line L214 (-21.2, -41.5) -> (-21.8, -41.5)
  line L215 (-21.8, -41.5) -> (-21.8, -45.5)
  line L216 (-23.5, -21.8) -> (-19.5, -21.8)
  line L217 (-19.5, -21.8) -> (-19.5, -21.2)
  line L218 (-19.5, -21.2) -> (-23.5, -21.2)
  line L219 (-23.5, -21.2) -> (-23.5, -21.8)
  line L220 (-21.8, -23.5) -> (-21.2, -23.5)
  line L221 (-21.2, -23.5) -> (-21.2, -19.5)
  line L222 (-21.2, -19.5) -> (-21.8, -19.5)
  line L223 (-21.8, -19.5) -> (-21.8, -23.5)
  line L224 (-45.5, -11.3) -> (-41.5, -11.3)
  line L225 (-41.5, -11.3) -> (-41.5, -10.7)
  line L226 (-41.5, -10.7) -> (-45.5, -10.7)
  line L227 (-45.5, -10.7) -> (-45.5, -11.3)
  line L228 (-43.8, -13) -> (-43.2, -13)
  line L229 (-43.2, -13) -> (-43.2, -9)
  line L230 (-43.2, -9) -> (-43.8, -9)
  line L231 (-43.8, -9) -> (-43.8, -13)
  line L232 (-45.5, 10.7) -> (-41.5, 10.7)
  line L233 (-41.5, 10.7) -> (-41.5, 11.3)
  line L234 (-41.5, 11.3) -> (-45.5, 11.3)
  line L235 (-45.5, 11.3) -> (-45.5, 10.7)
  line L236 (-43.8, 9) -> (-43.2, 9)
  line L237 (-43.2, 9) -> (-43.2, 13)
  line L238 (-43.2, 13) -> (-43.8, 13)
  line L239 (-43.8, 13) -> (-43.8, 9)
  line L240 (-23.5, -11.3) -> (-19.5, -11.3)
  line L241 (-19.5, -11.3) -> (-19.5, -10.7)
  line L242 (-19.5, -10.7) -> (-23.5, -10.7)
  line L243 (-23.5, -10.7) -> (-23.5, -11.3)
  line L244 (-21.8, -13) -> (-21.2, -13)
  line L245 (-21.2, -13) -> (-21.2, -9)
  line L246 (-21.2, -9) -> (-21.8, -9)
  line L247 (-21.8, -9) -> (-21.8, -13)
  line L248 (-23.5, 10.7) -> (-19.5, 10.7)
  line L249 (-19.5, 10.7) -> (-19.5, 11.3)
  line L250 (-19.5, 11.3) -> (-23.5, 11.3)
  line L251 (-23.5, 11.3) -> (-23.5, 10.7)
  line L252 (-21.8, 9) -> (-21.2, 9)
  line L253 (-21.2, 9) -> (-21.2, 13)
  line L254 (-21.2, 13) -> (-21.8, 13)
  line L255 (-21.8, 13) -> (-21.8, 9)
  line L256 (-45.5, 21.2) -> (-41.5, 21.2)
  line L257 (-41.5, 21.2) -> (-41.5, 21.8)
  line L258 (-41.5, 21.8) -> (-45.5, 21.8)
  line L259 (-45.5, 21.8) -> (-45.5, 21.2)
  line L260 (-43.8, 19.5) -> (-43.2, 19.5)
  line L261 (-43.2, 19.5) -> (-43.2, 23.5)
  line L262 (-43.2, 23.5) -> (-43.8, 23.5)
  line L263 (-43.8, 23.5) -> (-43.8, 19.5)
  line L264 (-45.5, 43.2) -> (-41.5, 43.2)
  line L265 (-41.5, 43.2) -> (-41.5, 43.8)
  line L266 (-41.5, 43.8) -> (-45.5, 43.8)
  line L267 (-45.5, 43.8) -> (-45.5, 43.2)
  line L268 (-43.8, 41.5) -> (-43.2, 41.5)
  line L269 (-43.2, 41.5) -> (-43.2, 45.5)
  line L270 (-43.2, 45.5) -> (-43.8, 45.5)
  line L271 (-43.8, 45.5) -> (-43.8, 41.5)
  line L272 (-23.5, 21.2) -> (-19.5, 21.2)
  line L273 (-19.5, 21.2) -> (-19.5, 21.8)
  line L274 (-19.5, 21.8) -> (-23.5, 21.8)
  line L275 (-23.5, 21.8) -> (-23.5, 21.2)
  line L276 (-21.8, 19.5) -> (-21.2, 19.5)
  line L277 (-21.2, 19.5) -> (-21.2, 23.5)
  line L278 (-21.2, 23.5) -> (-21.8, 23.5)
  line L279 (-21.8, 23.5) -> (-21.8, 19.5)
  line L280 (-23.5, 43.2) -> (-19.5, 43.2)
  line L281 (-19.5, 43.2) -> (-19.5, 43.8)
  line L282 (-19.5, 43.8) -> (-23.5, 43.8)
  line L283 (-23.5, 43.8) -> (-23.5, 43.2)
  line L284 (-21.8, 41.5) -> (-21.2, 41.5)
  line L285 (-21.2, 41.5) -> (-21.2, 45.5)
  line L286 (-21.2, 45.5) -> (-21.8, 45.5)
  line L287 (-21.8, 45.5) -> (-21.8, 41.5)
  line L288 (-45.5, 53.7) -> (-41.5, 53.7)
  line L289 (-41.5, 53.7) -> (-41.5, 54.3)
  line L290 (-41.5, 54.3) -> (-45.5, 54.3)
  line L291 (-45.5, 54.3) -> (-45.5, 53.7)
  line L292 (-43.8, 52) -> (-43.2, 52)
  line L293 (-43.2, 52) -> (-43.2, 56)
  line L294 (-43.2, 56) -> (-43.8, 56)
  line L295 (-43.8, 56) -> (-43.8, 52)
  line L296 (-45.5, 75.7) -> (-41.5, 75.7)
  line L297 (-41.5, 75.7) -> (-41.5, 76.3)
  line L298 (-41.5, 76.3) -> (-45.5, 76.3)
  line L299 (-45.5, 76.3) -> (-45.5, 75.7)
  line L300 (-43.8, 74) -> (-43.2, 74)
  line L301 (-43.2, 74) -> (-43.2, 78)
  line L302 (-43.2, 78) -> (-43.8, 78)
  line L303 (-43.8, 78) -> (-43.8, 74)
  line L304 (-23.5, 53.7) -> (-19.5, 53.7)
  line L305 (-19.5, 53.7) -> (-19.5, 54.3)
  line L306 (-19.5, 54.3) -> (-23.5, 54.3)
  line L307 (-23.5, 54.3) -> (-23.5, 53.7)
  line L308 (-21.8, 52) -> (-21.2, 52)
  line L309 (-21.2, 52) -> (-21.2, 56)
  line L310 (-21.2, 56) -> (-21.8, 56)
  line L311 (-21.8, 56) -> (-21.8, 52)
  line L312 (-23.5, 75.7) -> (-19.5, 75.7)
  line L313 (-19.5, 75.7) -> (-19.5, 76.3)
  line L314 (-19.5, 76.3) -> (-23.5, 76.3)
  line L315 (-23.5, 76.3) -> (-23.5, 75.7)
  line L316 (-21.8, 74) -> (-21.2, 74)
  line L317 (-21.2, 74) -> (-21.2, 78)
  line L318 (-21.2, 78) -> (-21.8, 78)
  line L319 (-21.8, 78) -> (-21.8, 74)
  line L320 (-13, -76.3) -> (-9, -76.3)
  line L321 (-9, -76.3) -> (-9, -75.7)
  line L322 (-9, -75.7) -> (-13, -75.7)
  line L323 (-13, -75.7) -> (-13, -76.3)
  line L324 (-11.3, -78) -> (-10.7, -78)
  line L325 (-10.7, -78) -> (-10.7, -74)
  line L326 (-10.7, -74) -> (-11.3, -74)
  line L327 (-11.3, -74) -> (-11.3, -78)
  line L328 (-13, -54.3) -> (-9, -54.3)
  line L329 (-9, -54.3) -> (-9, -53.7)
  line L330 (-9, -53.7) -> (-13, -53.7)
  line L331 (-13, -53.7) -> (-13, -54.3)
  line L332 (-11.3, -56) -> (-10.7, -56)
  line L333 (-10.7, -56) -> (-10.7, -52)
  line L334 (-10.7, -52) -> (-11.3, -52)
  line L335 (-11.3, -52) -> (-11.3, -56)
  line L336 (9, -76.3) -> (13, -76.3)
  line L337 (13, -76.3) -> (13, -75.7)
  line L338 (13, -75.7) -> (9, -75.7)
  line L339 (9, -75.7) -> (9, -76.3)
  line L340 (10.7, -78) -> (11.3, -78)
  line L341 (11.3, -78) -> (11.3, -74)
  line L342 (11.3, -74) -> (10.7, -74)
  line L343 (10.7, -74) -> (10.7, -78)
  line L344 (9, -54.3) -> (13, -54.3)
  line L345 (13, -54.3) -> (13, -53.7)
  line L346 (13, -53.7) -> (9, -53.7)
  line L347 (9, -53.7) -> (9, -54.3)
  line L348 (10.7, -56) -> (11.3, -56)
  line L349 (11.3, -56) -> (11.3, -52)
  line L350 (11.3, -52) -> (10.7, -52)
  line L351 (10.7, -52) -> (10.7, -56)
  line L352 (-13, -43.8) -> (-9, -43.8)
  line L353 (-9, -43.8) -> (-9, -43.2)
  line L354 (-9, -43.2) -> (-13, -43.2)
  line L355 (-13, -43.2) -> (-13, -43.8)
  line L356 (-11.3, -45.5) -> (-10.7, -45.5)
  line L357 (-10.7, -45.5) -> (-10.7, -41.5)
  line L358 (-10.7, -41.5) -> (-11.3, -41.5)
  line L359 (-11.3, -41.5) -> (-11.3, -45.5)
  line L360 (-13, -21.8) -> (-9, -21.8)
  line L361 (-9, -21.8) -> (-9, -21.2)
  line L362 (-9, -21.2) -> (-13, -21.2)
  line L363 (-13, -21.2) -> (-13, -21.8)
  line L364 (-11.3, -23.5) -> (-10.7, -23.5)
  line L365 (-10.7, -23.5) -> (-10.7, -19.5)
  line L366 (-10.7, -19.5) -> (-11.3, -19.5)
  line L367 (-11.3, -19.5) -> (-11.3, -23.5)
  line L368 (9, -43.8) -> (13, -43.8)
  line L369 (13, -43.8) -> (13, -43.2)
  line L370 (13, -43.2) -> (9, -43.2)
  line L371 (9, -43.2) -> (9, -43.8)
  line L372 (10.7, -45.5) -> (11.3, -45.5)
  line L373 (11.3, -45.5) -> (11.3, -41.5)
  line L374 (11.3, -41.5) -> (10.7, -41.5)
  line L375 (10.7, -41.5) -> (10.7, -45.5)
  line L376 (9, -21.8) -> (13, -21.8)
  line L377 (13, -21.8) -> (13, -21.2)